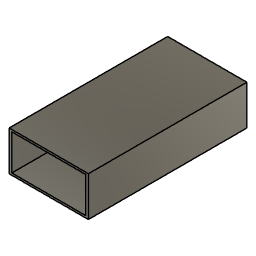
eindstuk profiel (Autodesk Fusion 360 design; units mm, degrees)
Autodesk Fusion 360 part; units mm, degrees
sketch "Sketch3" plane through (0, 0, 0) normal (0, 0, 1) x (1, 0, 0)
  line L0 (0, 0) -> (30, 0)
  line L1 (30, 0) -> (30, 60)
  line L2 (30, 60) -> (0, 60)
  line L3 (0, 60) -> (0, 0)
  dimension "d9" = 30
  dimension "d10" = 60
  constraint horizontal L0
  constraint vertical L1
  constraint horizontal L2
  constraint vertical L3
  constraint coincident L0.start L3.end
  measures "d9" distance of L0.start L0.end
  measures "d10" distance of L0.start L2.end
extrude "Extrude3" add sketch "Sketch3" along normal blind 15
sketch "Sketch4" plane through (0, 0, 0) normal (0, -1, 0) x (1, 0, 0)
  line L0 (0, 0) -> (30, 0)
  line L1 (30, 0) -> (30, 15)
  line L2 (30, 15) -> (0, 15)
  line L3 (0, 15) -> (0, 0)
  line L4 (1, 14.25) -> (29, 14.25)
  line L5 (29, 14.25) -> (29, 0.75)
  line L6 (29, 0.75) -> (1, 0.75)
  line L7 (1, 0.75) -> (1, 14.25)
  line L8 (29, 14.25) -> (30, 14.25)
  line L9 (29, 0.75) -> (29, 0)
  line L10 (29, 14.25) -> (29, 15)
  line L11 (1, 14.25) -> (0, 14.25)
  dimension "d13" = 28
  dimension "d14" = 13.5
  constraint horizontal L4
  constraint vertical L5
  constraint horizontal L6
  constraint vertical L7
  constraint coincident L1 L8.end
  constraint perpendicular L1 L8
  constraint coincident L0 L9.end
  constraint perpendicular L0 L9
  constraint coincident L2 L10.end
  constraint perpendicular L2 L10
  constraint coincident L3 L11.end
  constraint perpendicular L3 L11
  constraint equal L8 L11
  constraint equal L9 L10
  measures "d13" distance of L4.start L4.end
  measures "d14" distance of L4.start L6.end
extrude "Extrude4" cut sketch "Sketch4" against normal blind 30 contours L4 L5 L6 L7
sketch "Sketch5" plane through (0, 0, 0) normal (0, 0, -1) x (1, 0, 0)
  line L0 (0, 0) -> (0, -60)
  line L1 (0, -60) -> (30, -60)
  line L2 (30, -60) -> (30, 0)
  line L3 (30, 0) -> (0, 0)
  line L4 (0, -30) -> (30, -30)
  line L5 (1, -31) -> (29, -31)
  line L6 (29, -31) -> (29, -59)
  line L7 (29, -59) -> (1, -59)
  line L8 (1, -59) -> (1, -31)
  constraint midpoint L0 L4.start
  constraint midpoint L2 L4.end
  constraint horizontal L5
  constraint vertical L6
  constraint horizontal L7
  constraint vertical L8
extrude "Extrude5" cut sketch "Sketch5" against normal blind 14 contours L5 L6 L7 L8
sketch "Sketch6" plane through (0, 30, 0) normal (0, -1, 0) x (1, 0, 0)
  line L0 (1, 0.75) -> (29, 0.75)
  line L1 (29, 0.75) -> (29, 14.25)
  line L2 (29, 14.25) -> (1, 14.25)
  line L3 (1, 14.25) -> (1, 0.75)
  line L4 (1, 0.75) -> (29, 0.75)
  line L5 (29, 0.75) -> (29, 10.75)
  line L6 (29, 10.75) -> (1, 10.75)
  line L7 (1, 10.75) -> (1, 0.75)
  dimension "d19" = 10
  constraint horizontal L4
  constraint vertical L5
  constraint horizontal L6
  constraint vertical L7
  constraint coincident L0.start L3.end
  measures "d19" distance of L0.start L6.end
extrude "Extrude6" cut sketch "Sketch6" against normal blind 5 contours L0 L1 L3 L4 L5 L6 L7
